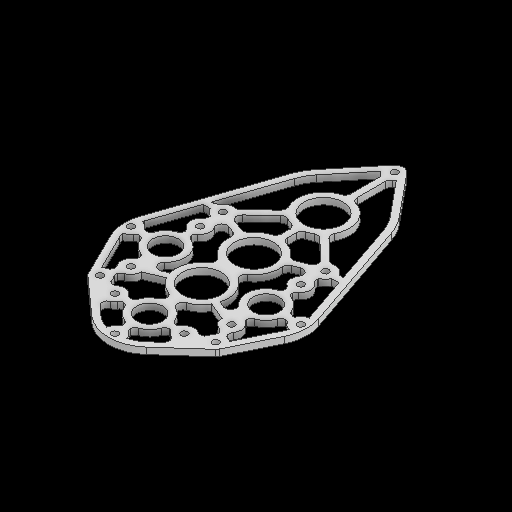
# Autodesk Inventor part: gb5_001_plate
Saved by Autodesk Inventor 2027.1 (Build 311270010, 270A)
## iProperties
Created: 2026-10-31
Part Number: gb5_001_plate
Material: Generic
Document SubType Name: Modeling
Designer: Stanley Ruangsuwan
Density: 1 g/cm^3
Appearance: Default
Author: Stanley Ruangsuwan
Autodesk Inventor part; units mm, degrees
ref_plane "YZ Plane" through (0, 0, 0) normal (1, 0, 0) x (0, 1, 0)
ref_plane "XZ Plane" through (0, 0, 0) normal (0, 1, 0) x (-1, 0, 0)
ref_plane "XY Plane" through (0, 0, 0) normal (0, 0, 1) x (1, 0, 0)
sketch "Sketch1" plane through (0, 0, 0) normal (0, 1, 0) x (-1, 0, 0)
  circle A0 centre (36.7799, -18.3459) radius 25.4 construction
  circle A1 centre (0, 30.0609) radius 25.4 construction
  circle A2 centre (-36.7799, -18.3459) radius 25.4 construction
  circle A3 centre (36.7799, -18.3459) radius 30.0609
  circle A4 centre (-36.7799, -18.3459) radius 30.0609
  circle A5 centre (0, 30.0609) radius 30.0609
  circle A6 centre (36.7799, -18.3459) radius 13.97 construction
  circle A7 centre (-36.7799, -18.3459) radius 13.97 construction
  circle A8 centre (0, 30.0609) radius 13.97 construction
  circle A9 centre (0, -8.1153) radius 26.67 construction
  circle A10 centre (0, -8.1153) radius 14.2875
  circle A11 centre (0, -46.2915) radius 13.97 construction
  circle A12 centre (0, -97.1677) radius 39.37
  circle A13 centre (36.7799, -43.7459) radius 2.4892
  circle A14 centre (54.7404, -36.3064) radius 2.4892
  circle A15 centre (62.1799, -18.3459) radius 2.4892
  circle A16 centre (54.7404, -0.3853) radius 2.4892
  circle A17 centre (36.7799, 7.0541) radius 2.4892
  line L0 (0, -8.1153) -> (0, -46.2915) construction
  circle A18 centre (-36.7799, -43.7459) radius 2.4892
  circle A19 centre (-54.7404, -36.3064) radius 2.4892
  circle A20 centre (-62.1799, -18.3459) radius 2.4892
  circle A21 centre (-54.7404, -0.3853) radius 2.4892
  circle A22 centre (-36.7799, 7.0541) radius 2.4892
  circle A23 centre (0, -46.2915) radius 14.2875
  circle A24 centre (0, -97.1677) radius 14.2875
  circle A25 centre (0, 30.0609) radius 9.525
  circle A26 centre (36.7799, -18.3459) radius 9.525
  circle A27 centre (-36.7799, -18.3459) radius 9.525
  circle A28 centre (25.4, 30.0609) radius 2.4892
  circle A29 centre (17.9605, 48.0214) radius 2.4892
  circle A30 centre (0, 55.4609) radius 2.4892
  circle A31 centre (-17.9605, 48.0214) radius 2.4892
  circle A32 centre (-25.4, 30.0609) radius 2.4892
  circle A33 centre (37.5551, -61.0997) radius 2.4892
  circle A34 centre (37.5551, -61.0997) radius 6.35 construction
  line L1 (32.9752, -65.4983) -> (28.3953, -69.8968) construction
  line L2 (37.44, -54.7508) -> (37.3249, -48.4018) construction
  circle A35 centre (-37.5551, -61.0997) radius 2.4892
  circle A36 centre (-37.5551, -61.0997) radius 6.35 construction
  line L3 (-32.9752, -65.4983) -> (-28.3953, -69.8968) construction
  line L4 (-37.44, -54.7508) -> (-37.3249, -48.4018) construction
  circle A37 centre (42.3367, 24.0525) radius 2.4892
  circle A38 centre (42.3367, 24.0525) radius 6.35
  line L5 (41.5115, 17.7563) -> (40.6863, 11.4601) construction
  line L6 (36.0497, 24.9447) -> (29.7627, 25.837) construction
  circle A39 centre (-42.3367, 24.0525) radius 2.4892
  circle A40 centre (-42.3367, 24.0525) radius 6.35
  line L7 (20.0185, 52.4867) -> (46.5653, 28.7896)
  line L8 (48.0338, 26.857) -> (63.75, -5.0693)
  line L9 (-20.0185, 52.4867) -> (-46.5653, 28.7896)
  line L10 (-48.0338, 26.857) -> (-63.75, -5.0693)
  circle A41 centre (0, -149.2377) radius 2.4892
  circle A42 centre (0, -149.2377) radius 6.35
  line L11 (0, -142.8877) -> (0, -136.5377) construction
  line L12 (-65.225, -28.0686) -> (-37.2539, -109.9014)
  line L13 (65.225, -28.0686) -> (37.2539, -109.9014)
  line L14 (30.4414, -122.134) -> (4.9099, -153.2645)
  line L15 (-30.4414, -122.134) -> (-4.9099, -153.2645)
  point P0 (0, 0)
  point P1 (36.2511, 22.2392)
  point P2 (36.3744, 26.2373)
  dimension "d1" = 50.8
  dimension "d5" = 60.1218
  dimension "d8" = 27.94
  dimension "d9" = 53.34
  dimension "d10" = 38.1762
  dimension "d11" = 38.1762
  dimension "d13" = 38.1762
  dimension "d14" = 28.575
  dimension "d15" = 60.7945
  dimension "d16" = 38.1762
  dimension "d17" = 78.74
  dimension "d18" = 50.8762
  dimension "d19" = 4.9784
  dimension "d22" = 180
  dimension "d29" = 28.575
  dimension "d31" = 19.05
  dimension "d33" = 4.9784
  dimension "d36" = 180
  dimension "d38" = 4.9784
  dimension "d41" = 12.7
  dimension "d42" = 6.35
  dimension "d43" = 4.9784
  dimension "d44" = 12.7
  dimension "d47" = 4.9784
  dimension "d48" = 12.7
  constraints: 41 centre point, 32 end point, 31 point on circle, 17 coincident, 16 tangent, 13 symmetric about line, 10 point on line, 8 equal radius, 8 vertical alignment, 4 equal length, 3 horizontal alignment, 2 vertical, 32 other
  measures "d5" diameter of A5
  measures "d8" diameter of A8
  measures "d9" diameter of A9
  measures "d10" distance of A9.centre A6.centre
  measures "d11" distance of A7.centre A9.centre
  measures "d13" distance of A8.centre A9.centre
  measures "d14" diameter of A10
  measures "d15" distance of A5.centre A7.centre
  measures "d16" distance of A9.centre L0.end
  measures "d17" diameter of A12
  measures "d18" distance of L0.end A12.centre
  measures "d19" diameter of A13
  measures "d29" diameter of A24
  measures "d31" diameter of A26
  measures "d33" diameter of A28
  measures "d38" diameter of A33
  measures "d41" diameter of A34
  measures "d42" distance of L1.start L1.end
  measures "d43" diameter of A37
  measures "d44" diameter of A38
  measures "d47" diameter of A41
  measures "d48" diameter of A42
extrude "Extrusion1" add sketch "Sketch1" along normal blind 4.7625 contours A3 A10 | A3 A10 A5 L7 A38 L8 | L13 A12 A23 L12 A4 A10 A3 | A38 | A12 A23 | A10 A5 | A4 A10 | L14 A42 L15 A12 | A10 A4 L10 A40 L9 A5 | A42 | A40 picked at (29.5618, -37.6747) picked at (-8.372, -68.1952) picked at (-19.4323, 22.8031) picked at (-29.5618, -37.6747)
sketch "Sketch2" plane through (0, 4.7625, 0) normal (0, 1, 0) x (1, 0, 0)
  arc A0 (46.5653, -28.7896) -> (48.0338, -26.857) centre (42.3367, -24.0525) ccw projected
  line L0 (48.0338, -26.857) -> (63.75, 5.0693) projected
  arc A1 (63.75, 5.0693) -> (65.225, 28.0686) centre (36.7799, 18.3459) ccw projected
  line L1 (65.225, 28.0686) -> (37.2539, 109.9014) projected
  arc A2 (37.2539, 109.9014) -> (30.4414, 122.134) centre (0, 97.1677) ccw projected
  line L2 (30.4414, 122.134) -> (4.9099, 153.2645) projected
  arc A3 (4.9099, 153.2645) -> (-4.9099, 153.2645) centre (0, 149.2377) ccw projected
  line L3 (-4.9099, 153.2645) -> (-30.4414, 122.134) projected
  arc A4 (-30.4414, 122.134) -> (-37.2539, 109.9014) centre (0, 97.1677) ccw projected
  line L4 (-37.2539, 109.9014) -> (-65.225, 28.0686) projected
  arc A5 (-65.225, 28.0686) -> (-63.75, 5.0693) centre (-36.7799, 18.3459) ccw projected
  line L5 (-63.75, 5.0693) -> (-48.0338, -26.857) projected
  arc A6 (-48.0338, -26.857) -> (-46.5653, -28.7896) centre (-42.3367, -24.0525) ccw projected
  line L6 (-46.5653, -28.7896) -> (-20.0185, -52.4867) projected
  arc A7 (-20.0185, -52.4867) -> (20.0185, -52.4867) centre (0, -30.0609) ccw projected
  line L7 (20.0185, -52.4867) -> (46.5653, -28.7896) projected
  circle A8 centre (42.3367, -24.0525) radius 2.4892 projected
  circle A9 centre (-42.3367, -24.0525) radius 2.4892 projected
  circle A10 centre (0, -30.0609) radius 9.525 projected
  circle A11 centre (-25.4, -30.0609) radius 2.4892 projected
  circle A12 centre (-17.9605, -48.0214) radius 2.4892 construction
  circle A13 centre (0, -55.4609) radius 2.4892 projected
  circle A14 centre (17.9605, -48.0214) radius 2.4892 construction
  circle A15 centre (25.4, -30.0609) radius 2.4892 projected
  circle A16 centre (0, 46.2915) radius 14.2875 projected
  circle A17 centre (37.5551, 61.0997) radius 2.4892 projected
  circle A18 centre (-37.5551, 61.0997) radius 2.4892 projected
  circle A19 centre (-36.7799, 18.3459) radius 9.525 projected
  circle A20 centre (-36.7799, -7.0541) radius 2.4892 projected
  circle A21 centre (-54.7404, 0.3853) radius 2.4892 construction
  circle A22 centre (-62.1799, 18.3459) radius 2.4892 projected
  circle A23 centre (-54.7404, 36.3064) radius 2.4892 construction
  circle A24 centre (-36.7799, 43.7459) radius 2.4892 projected
  circle A25 centre (36.7799, 18.3459) radius 9.525 projected
  circle A26 centre (36.7799, -7.0541) radius 2.4892 projected
  circle A27 centre (54.7404, 0.3853) radius 2.4892 construction
  circle A28 centre (62.1799, 18.3459) radius 2.4892 projected
  circle A29 centre (54.7404, 36.3064) radius 2.4892 construction
  circle A30 centre (36.7799, 43.7459) radius 2.4892 projected
  circle A31 centre (0, 97.1677) radius 14.2875 projected
  circle A32 centre (0, 8.1153) radius 14.2875 projected
  circle A33 centre (0, 149.2377) radius 2.4892 projected
  line L8 (32.7473, 108.361) -> (60.7185, 26.5283)
  arc A34 (59.4772, 7.1727) -> (60.7185, 26.5283) centre (36.7799, 18.3459) ccw
  line L9 (59.4772, 7.1727) -> (43.7609, -24.7536)
  arc A35 (43.3938, -25.2367) -> (43.7609, -24.7536) centre (42.3367, -24.0525) ccw
  line L10 (43.3938, -25.2367) -> (16.847, -48.9339)
  arc A36 (-16.847, -48.9339) -> (16.847, -48.9339) centre (0, -30.0609) ccw
  line L11 (-16.847, -48.9339) -> (-43.3938, -25.2367)
  arc A37 (-43.7609, -24.7536) -> (-43.3938, -25.2367) centre (-42.3367, -24.0525) ccw
  line L12 (-43.7609, -24.7536) -> (-59.4772, 7.1727)
  arc A38 (-60.7185, 26.5283) -> (-59.4772, 7.1727) centre (-36.7799, 18.3459) ccw
  line L13 (-60.7185, 26.5283) -> (-32.7473, 108.361)
  arc A39 (-26.759, 119.1139) -> (-32.7473, 108.361) centre (0, 97.1677) ccw
  line L14 (-26.759, 119.1139) -> (-1.2275, 150.2444)
  arc A40 (1.2275, 150.2444) -> (-1.2275, 150.2444) centre (0, 149.2377) ccw
  line L15 (1.2275, 150.2444) -> (26.759, 119.1139)
  arc A41 (32.7473, 108.361) -> (26.759, 119.1139) centre (0, 97.1677) ccw
  circle A42 centre (62.1799, 18.3459) radius 7.2517
  circle A43 centre (36.7799, -7.0541) radius 7.2517
  circle A44 centre (36.7799, 43.7459) radius 7.2517
  circle A45 centre (37.5551, 61.0997) radius 7.2517
  circle A46 centre (0, -55.4609) radius 7.2517
  circle A47 centre (25.4, -30.0609) radius 7.2517
  circle A48 centre (42.3367, -24.0525) radius 7.2517
  circle A49 centre (0, 149.2377) radius 7.2517
  line L16 (0, 32.004) -> (0, 60.579)
  circle A50 centre (36.7799, 18.3459) radius 14.2875
  circle A51 centre (0, -30.0609) radius 14.2875
  circle A52 centre (0, 8.1153) radius 19.05
  circle A53 centre (0, 46.2915) radius 19.05
  circle A54 centre (0, 97.1677) radius 19.05
  circle A55 centre (-62.1799, 18.3459) radius 7.2517
  circle A56 centre (-36.7799, -7.0541) radius 7.2517
  circle A57 centre (-36.7799, 43.7459) radius 7.2517
  circle A58 centre (-37.5551, 61.0997) radius 7.2517
  circle A59 centre (-25.4, -30.0609) radius 7.2517
  circle A60 centre (-42.3367, -24.0525) radius 7.2517
  circle A61 centre (-36.7799, 18.3459) radius 14.2875
  line L17 (51.0674, 18.3459) -> (54.9282, 18.3459)
  line L18 (36.7799, 4.0584) -> (36.7799, 0.1976)
  line L19 (36.7799, 32.6334) -> (36.7799, 36.4942)
  line L20 (23.0149, 14.5171) -> (18.3532, 13.2204)
  line L21 (30.076, -4.2892) -> (17.6109, 0.8519)
  line L22 (18.1483, -30.0609) -> (14.2875, -30.0609)
  line L23 (0, -44.3484) -> (0, -48.2092)
  line L24 (37.1035, 50.9903) -> (37.2315, 53.8553)
  line L25 (44.8068, 61.0997) -> (48.9017, 61.0997)
  line L26 (30.8089, 58.4397) -> (17.7221, 53.2794)
  line L27 (32.3249, 66.1229) -> (13.7397, 83.9721)
  line L28 (0, 116.2177) -> (0, 141.986)
  line L29 (-51.0674, 18.3459) -> (-54.9282, 18.3459)
  line L30 (-36.7799, 4.0584) -> (-36.7799, 0.1976)
  line L31 (-36.7799, 32.6334) -> (-36.7799, 36.4942)
  line L32 (-23.0149, 14.5171) -> (-18.3532, 13.2204)
  line L33 (-30.076, -4.2892) -> (-17.6109, 0.8519)
  line L34 (-18.1483, -30.0609) -> (-14.2875, -30.0609)
  line L35 (-37.1035, 50.9903) -> (-37.2315, 53.8553)
  line L36 (-44.8068, 61.0997) -> (-48.9017, 61.0997)
  line L37 (-30.8089, 58.4397) -> (-17.7221, 53.2794)
  line L38 (-32.3249, 66.1229) -> (-13.7397, 83.9721)
  line L39 (-34.2643, 67.5618) -> (-15.2814, 85.7931)
  line L40 (-33.2285, 61.9534) -> (-11.9825, 82.3581)
  line L41 (-33.2285, 61.9534) -> (-16.7096, 55.4399)
  line L42 (-26.1954, 54.0609) -> (-18.4566, 51.0094)
  arc A62 (-28.7315, 66.2724) -> (-27.428, 59.6662) centre (-25.9607, 63.3874) ccw
  line L43 (-39.4644, 50.4823) -> (-39.6283, 54.1507)
  line L44 (-44.4047, 58.7185) -> (-49.7156, 58.7185)
  line L45 (-44.4047, 63.481) -> (-48.0877, 63.481)
  line L46 (-39.1611, 32.4335) -> (-39.1611, 36.8963)
  line L47 (-34.3986, 32.4335) -> (-34.3986, 36.8963)
  line L48 (-22.8539, 1.2653) -> (-18.3807, 3.1102)
  line L49 (-39.1611, 4.2582) -> (-39.1611, -0.2046)
  line L50 (-50.8675, 20.7271) -> (-55.3303, 20.7271)
  arc A63 (-26.1954, 54.0609) -> (-30.9039, 47.9956) centre (-27.6627, 50.3397) ccw
  arc A64 (-27.0733, 7.8618) -> (-22.8539, 1.2653) centre (-24.3707, 4.9428) ccw
  line L51 (-29.5398, -6.6439) -> (-16.5649, -1.2925)
  arc A65 (-39.1611, 1.2231) -> (-41.7542, 4.9522) centre (-43.1391, 1.2231) ccw
  arc A66 (-40.8864, -1.0772) -> (-39.1611, 2.2015) centre (-43.1391, 2.2015) ccw
  line L52 (-50.8675, 15.9646) -> (-55.3303, 15.9646)
  arc A67 (-56.203, 22.4524) -> (-52.9242, 20.7271) centre (-52.9242, 24.7051) ccw
  arc A68 (-52.9242, 15.9646) -> (-56.203, 14.2393) centre (-52.9242, 11.9866) ccw
  arc A69 (-50.1735, 13.3716) -> (-53.9026, 15.9646) centre (-53.9026, 11.9866) ccw
  arc A70 (-53.9026, 20.7271) -> (-50.1735, 23.3202) centre (-53.9026, 24.7051) ccw
  arc A71 (-46.8223, 63.481) -> (-43.5278, 65.2124) centre (-46.8223, 67.481) ccw
  arc A72 (-39.6616, 54.897) -> (-43.6577, 58.7185) centre (-43.6577, 54.7185) ccw
  arc A73 (-41.155, 49.529) -> (-39.5723, 52.8975) centre (-43.5683, 52.719) ccw
  arc A74 (-39.1611, 34.4787) -> (-40.8926, 37.7732) centre (-43.1611, 34.4787) ccw
  arc A75 (-41.7653, 31.7353) -> (-39.1611, 35.4839) centre (-43.1611, 35.4839) ccw
  arc A76 (-32.6672, 37.7732) -> (-34.3986, 34.4787) centre (-30.3986, 34.4787) ccw
  arc A77 (-34.3986, 35.4839) -> (-31.7944, 31.7353) centre (-30.3986, 35.4839) ccw
  arc A78 (-17.6243, 83.5429) -> (-16.8558, 88.2916) centre (-20.395, 86.4278) ccw
  arc A79 (-9.5495, 80.6841) -> (-14.3254, 80.108) centre (-11.5547, 77.223) ccw
  arc A80 (-36.0962, 68.2032) -> (-32.5207, 69.2364) centre (-35.2914, 72.1214) ccw
  line L53 (-18.5504, -32.4422) -> (-14.0877, -32.4422)
  line L54 (-18.5504, -27.6797) -> (-14.0877, -27.6797)
  arc A81 (-19.4231, -25.9543) -> (-16.1444, -27.6797) centre (-16.1444, -23.7016) ccw
  arc A82 (-17.1228, -27.6797) -> (-13.3936, -25.0866) centre (-17.1228, -23.7016) ccw
  arc A83 (-13.3936, -35.0352) -> (-17.1228, -32.4422) centre (-17.1228, -36.4202) ccw
  arc A84 (-16.1444, -32.4422) -> (-19.4231, -34.1675) centre (-16.1444, -36.4202) ccw
  line L55 (-2.3813, 116.0683) -> (-2.3813, 142.3881)
  arc A85 (-2.3813, 139.9705) -> (-4.1127, 143.265) centre (-6.3813, 139.9705) ccw
  arc A86 (-5.2739, 115.4731) -> (-2.3813, 119.3168) centre (-6.3813, 119.3168) ccw
  line L56 (34.2643, 67.5618) -> (15.2814, 85.7931)
  line L57 (33.2285, 61.9534) -> (11.9825, 82.3581)
  line L58 (33.2285, 61.9534) -> (16.7096, 55.4399)
  line L59 (26.1954, 54.0609) -> (18.4566, 51.0094)
  arc A87 (27.428, 59.6662) -> (28.7315, 66.2724) centre (25.9607, 63.3874) ccw
  line L60 (39.4644, 50.4823) -> (39.6283, 54.1507)
  line L61 (44.4047, 58.7185) -> (49.7156, 58.7185)
  line L62 (44.4047, 63.481) -> (48.0877, 63.481)
  line L63 (39.1611, 32.4335) -> (39.1611, 36.8963)
  line L64 (34.3986, 32.4335) -> (34.3986, 36.8963)
  line L65 (39.1611, 4.2582) -> (39.1611, -0.2046)
  line L66 (50.8675, 20.7271) -> (55.3303, 20.7271)
  arc A88 (30.9039, 47.9956) -> (26.1954, 54.0609) centre (27.6627, 50.3397) ccw
  arc A89 (22.8539, 1.2653) -> (27.0733, 7.8618) centre (24.3707, 4.9428) ccw
  line L67 (29.5398, -6.6439) -> (16.5649, -1.2925)
  arc A90 (41.7542, 4.9522) -> (39.1611, 1.2231) centre (43.1391, 1.2231) ccw
  arc A91 (39.1611, 2.2015) -> (40.8864, -1.0772) centre (43.1391, 2.2015) ccw
  line L68 (50.8675, 15.9646) -> (55.3303, 15.9646)
  arc A92 (56.203, 14.2393) -> (52.9242, 15.9646) centre (52.9242, 11.9866) ccw
  arc A93 (53.9026, 15.9646) -> (50.1735, 13.3716) centre (53.9026, 11.9866) ccw
  arc A94 (50.1735, 23.3202) -> (53.9026, 20.7271) centre (53.9026, 24.7051) ccw
  arc A95 (43.5278, 65.2124) -> (46.8223, 63.481) centre (46.8223, 67.481) ccw
  arc A96 (43.6577, 58.7185) -> (39.6616, 54.897) centre (43.6577, 54.7185) ccw
  arc A97 (39.5723, 52.8975) -> (41.155, 49.529) centre (43.5683, 52.719) ccw
  arc A98 (40.8926, 37.7732) -> (39.1611, 34.4787) centre (43.1611, 34.4787) ccw
  arc A99 (39.1611, 35.4839) -> (41.7653, 31.7353) centre (43.1611, 35.4839) ccw
  arc A100 (34.3986, 34.4787) -> (32.6672, 37.7732) centre (30.3986, 34.4787) ccw
  arc A101 (31.7944, 31.7353) -> (34.3986, 35.4839) centre (30.3986, 35.4839) ccw
  arc A102 (16.8558, 88.2916) -> (17.6243, 83.5429) centre (20.395, 86.4278) ccw
  arc A103 (14.3254, 80.108) -> (9.5495, 80.6841) centre (11.5547, 77.223) ccw
  arc A104 (32.5207, 69.2364) -> (36.0962, 68.2032) centre (35.2914, 72.1214) ccw
  line L69 (18.5504, -32.4422) -> (14.0877, -32.4422)
  arc A105 (16.1444, -27.6797) -> (19.4231, -25.9543) centre (16.1444, -23.7016) ccw
  arc A106 (13.3936, -25.0866) -> (17.1228, -27.6797) centre (17.1228, -23.7016) ccw
  arc A107 (17.1228, -32.4421) -> (13.3936, -35.0352) centre (17.1228, -36.4202) ccw
  arc A108 (19.4231, -34.1675) -> (16.1444, -32.4422) centre (16.1444, -36.4202) ccw
  line L70 (2.3812, 116.0683) -> (2.3812, 142.3881)
  arc A109 (4.1127, 143.265) -> (2.3812, 139.9705) centre (6.3812, 139.9705) ccw
  arc A110 (2.3812, 119.3168) -> (5.2739, 115.4731) centre (6.3812, 119.3168) ccw
  line L71 (22.8539, 1.2653) -> (18.3807, 3.1102)
  line L72 (-2.3813, -44.1486) -> (-2.3813, -48.6113)
  line L73 (2.3812, -44.1486) -> (2.3812, -48.6113)
  line L74 (17.1228, -27.6797) -> (16.1444, -27.6797)
  arc A111 (4.9743, -43.4545) -> (2.3813, -47.1837) centre (6.3593, -47.1837) ccw
  arc A112 (2.3813, -46.2053) -> (4.1066, -49.484) centre (6.3593, -46.2053) ccw
  arc A113 (-19.7316, 56.6315) -> (-15.0948, 57.9125) centre (-18.2643, 60.3527) ccw
  arc A114 (-18.964, 48.1001) -> (-21.4786, 52.201) centre (-22.9459, 48.4798) ccw
  arc A115 (15.0948, 57.9125) -> (19.7316, 56.6315) centre (18.2643, 60.3527) ccw
  arc A116 (21.4786, 52.201) -> (18.964, 48.1001) centre (22.9459, 48.4798) ccw
  arc A117 (-2.3812, -47.1837) -> (-4.9743, -43.4545) centre (-6.3593, -47.1837) ccw
  arc A118 (-4.1066, -49.484) -> (-2.3812, -46.2053) centre (-6.3593, -46.2053) ccw
  line L75 (-39.0331, -13.9469) -> (-40.0834, -17.1597)
  line L76 (-32.2344, -27.6363) -> (-35.5023, -26.477)
  line L77 (-41.1716, -12.8248) -> (-42.4717, -16.802)
  line L78 (-36.6448, -14.3046) -> (-37.945, -18.2818)
  line L79 (-31.0592, -25.5266) -> (-35.0851, -24.0984)
  line L80 (-32.6516, -30.015) -> (-36.6774, -28.5868)
  arc A119 (-41.9192, -15.1117) -> (-42.5403, -11.4592) centre (-45.7003, -13.8756) ccw
  arc A120 (-43.9689, -16.9868) -> (-41.9192, -15.1117) centre (-44.6049, -14.2337) ccw
  arc A121 (-35.2325, -22.597) -> (-33.4091, -24.6929) centre (-32.4644, -22.0299) ccw
  arc A122 (-35.0014, -29.1814) -> (-37.738, -29.6596) centre (-35.9462, -31.8444) ccw
  arc A123 (-32.5041, -31.5163) -> (-34.3275, -29.4204) centre (-35.2723, -32.0834) ccw
  arc A124 (-32.7352, -24.932) -> (-29.9986, -24.4538) centre (-31.7905, -22.269) ccw
  arc A125 (-34.7337, -14.0112) -> (-37.3924, -16.5915) centre (-33.6113, -17.8276) ccw
  arc A126 (-37.3924, -16.5915) -> (-36.8461, -19.3153) centre (-34.7066, -17.4695) ccw
  line L81 (39.0331, -13.9469) -> (40.0834, -17.1597)
  line L82 (32.2344, -27.6363) -> (35.5023, -26.477)
  line L83 (41.1716, -12.8248) -> (42.4717, -16.802)
  line L84 (36.6448, -14.3046) -> (37.945, -18.2818)
  line L85 (31.0592, -25.5266) -> (35.0851, -24.0984)
  line L86 (32.6516, -30.015) -> (36.6774, -28.5868)
  arc A127 (42.5403, -11.4592) -> (41.9192, -15.1117) centre (45.7003, -13.8756) ccw
  arc A128 (41.9192, -15.1117) -> (43.9689, -16.9868) centre (44.6049, -14.2337) ccw
  arc A129 (33.4091, -24.6929) -> (35.2325, -22.597) centre (32.4644, -22.0299) ccw
  arc A130 (37.738, -29.6596) -> (35.0014, -29.1814) centre (35.9462, -31.8444) ccw
  arc A131 (34.3275, -29.4204) -> (32.5041, -31.5163) centre (35.2723, -32.0834) ccw
  arc A132 (29.9986, -24.4538) -> (32.7352, -24.932) centre (31.7905, -22.269) ccw
  arc A133 (37.3924, -16.5915) -> (34.7337, -14.0112) centre (33.6113, -17.8276) ccw
  arc A134 (36.8461, -19.3153) -> (37.3924, -16.5915) centre (34.7066, -17.4695) ccw
  line L87 (0, 97.1677) -> (0, -30.0609)
  line L88 (-2.3813, 78.2671) -> (-2.3812, -15.9732)
  line L89 (2.3812, 78.2671) -> (2.3813, -15.9732)
  arc A135 (-2.3813, 75.0186) -> (-5.2739, 78.8623) centre (-6.3813, 75.0186) ccw
  arc A136 (-5.2739, 64.5969) -> (-2.3813, 68.4406) centre (-6.3813, 68.4406) ccw
  arc A137 (-10.6786, 23.8909) -> (-10.6786, 30.5159) centre (-12.9208, 27.2034) ccw
  arc A138 (-6.1078, -17.1447) -> (-6.4595, -9.8061) centre (-7.8083, -13.5485) ccw
  arc A139 (5.2739, 78.8623) -> (2.3812, 75.0186) centre (6.3812, 75.0186) ccw
  arc A140 (2.3812, 68.4406) -> (5.2739, 64.5969) centre (6.3812, 68.4406) ccw
  arc A141 (10.6786, 30.5159) -> (10.6786, 23.8909) centre (12.9208, 27.2034) ccw
  arc A142 (6.4595, -9.8061) -> (6.1078, -17.1447) centre (7.8083, -13.5485) ccw
  arc A143 (-22.3185, -36.6253) -> (-23.2771, -43.194) centre (-20.628, -40.2263) ccw
  arc A144 (23.2771, -43.194) -> (22.3185, -36.6253) centre (20.628, -40.2263) ccw
  point P0 (0, 0)
  point P1 (36.7799, 34.5638)
  point P2 (52.9978, 18.3459)
  point P3 (0, 46.2915)
  point P4 (-61.0433, 11.1838)
  point P5 (-46.886, -18.4053)
  point P6 (-38.1152, -29.9487)
  point P7 (-7.1621, -54.3243)
  point P8 (-61.0433, 25.5079)
  point P9 (-5.7146, 144.7733)
  point P10 (5.7146, 144.7733)
  point P11 (4.1127, 143.265)
  point P12 (5.2739, 115.4731)
  point P13 (16.8558, 88.2916)
  point P14 (36.0962, 68.2032)
  point P15 (43.5278, 65.2124)
  point P16 (48.0877, 63.481)
  point P17 (15.0948, 57.9125)
  point P18 (9.5495, 80.6841)
  point P19 (61.0433, 25.5079)
  point P20 (49.7156, 58.7185)
  point P21 (41.155, 49.529)
  point P22 (50.1735, 23.3202)
  point P23 (7.1621, -54.3243)
  point P24 (38.1152, -29.9487)
  point P25 (46.886, -18.4053)
  point P26 (61.0433, 11.1838)
  point P27 (56.203, 14.2393)
  point P28 (50.1735, 13.3716)
  point P29 (40.8864, -1.0772)
  point P30 (13.3936, -35.0352)
  point P31 (16.5649, -1.2925)
  point P32 (13.3936, -25.0866)
  point P33 (21.4786, 52.201)
  point P34 (18.964, 48.1001)
  point P35 (-32.6672, 37.7732)
  point P36 (-34.3986, 34.4787)
  point P37 (-34.3986, 35.4839)
  point P38 (-31.7944, 31.7353)
  point P39 (31.7944, 31.7353)
  point P40 (34.3986, 35.4839)
  point P41 (34.3986, 34.4787)
  point P42 (32.6672, 37.7732)
  point P43 (27.0733, 7.8618)
  point P44 (-16.6336, -32.4723)
  point P45 (-39.1913, 1.7123)
  point P46 (-53.4134, 15.9344)
  point P47 (-53.4134, 20.7573)
  point P48 (-39.1928, 34.9813)
  point P49 (39.1928, 34.9813)
  point P50 (39.1611, -0.2046)
  point P51 (2.4114, -46.6945)
  point P52 (16.6336, -32.4723)
  point P53 (53.4134, 15.9344)
  point P54 (39.1913, 1.7123)
  point P55 (16.6336, -27.6495)
  point P56 (-16.6336, -27.6495)
  point P57 (34.3669, 34.9813)
  point P58 (-34.3669, 34.9813)
  point P59 (-2.4114, -46.6945)
  point P60 (-4.9743, -43.4545)
  point P61 (-4.1066, -49.484)
  point P62 (42.5403, -11.4592)
  point P63 (2.3812, 75.0186)
  point P64 (2.3812, 68.4406)
  point P65 (5.2739, 64.5969)
  point P66 (6.4595, -9.8061)
  point P67 (6.1078, -17.1447)
  point P68 (36.8461, -19.3153)
  point P69 (34.7337, -14.0112)
  point P70 (-34.7337, -14.0112)
  point P71 (-36.8461, -19.3153)
  point P72 (23.2771, -43.194)
  point P73 (22.3185, -36.6253)
  dimension "d49" = 4.7625
  dimension "d50" = 4.7625
  dimension "d56" = 4.7625
  dimension "d57" = 4.7625
  dimension "d58" = 4.7625
  dimension "d59" = 2.3813
  dimension "d60" = 2.3813
  dimension "d61" = 2.3813
  dimension "d62" = 2.3813
  dimension "d63" = 4
  dimension "d66" = 2.3813
  dimension "d67" = 2.3813
  dimension "d68" = 2.3813
  dimension "d69" = 2.3813
  dimension "d70" = 2.3813
  dimension "d74" = 2.3813
  dimension "d75" = 2.3813
  dimension "d78" = 2.3813
  dimension "d79" = 4
  dimension "d81" = 2.3813
  dimension "d88" = 2.3813
  dimension "d89" = 2.3813
  dimension "d91" = 2.3813
  dimension "d92" = 2.3813
  dimension "d97" = 2.3813
  dimension "d98" = 2.3813
  dimension "d99" = 2.3813
  dimension "d100" = 2.3813
  dimension "d101" = 2.3813
  dimension "d102" = 2.3813
  constraints: 222 point on circle, 206 symmetric about line, 167 end point, 101 centre point, 85 point on line, 48 tangent, 37 equal radius, 23 parallel, 6 vertical, 4 coincident, 4 midpoint, 3 horizontal, 1 equal length, 1 horizontal alignment, 1 perpendicular, 1 vertical alignment, 190 other
  measures "d49" distance between parallel lines of L1 L8
  measures "d56" radial gap between concentric circles of A25 A50
  measures "d59" distance between parallel lines of L38 L39
  measures "d60" distance between parallel lines of L38 L40
  measures "d61" distance between parallel lines of L37 L41
  measures "d62" distance between parallel lines of L37 L42
  measures "d63" radius of A62
  measures "d66" distance between parallel lines of L35 L43
  measures "d67" distance between parallel lines of L36 L44
  measures "d68" distance between parallel lines of L36 L45
  measures "d69" distance between parallel lines of L31 L46
  measures "d70" distance between parallel lines of L31 L47
  measures "d74" distance between parallel lines of L33 L48
  measures "d75" distance between parallel lines of L30 L49
  measures "d78" distance between parallel lines of L29 L50
  measures "d79" radius of A63
  measures "d81" distance between parallel lines of L33 L51
  measures "d88" distance between parallel lines of L34 L53
  measures "d89" distance between parallel lines of L28 L55
  measures "d91" distance between parallel lines of L23 L72
  measures "d92" distance between parallel lines of L23 L73
  measures "d97" distance between parallel lines of L75 L77
  measures "d98" distance between parallel lines of L78 L75
  measures "d99" distance between parallel lines of L76 L79
  measures "d100" distance between parallel lines of L76 L80
  measures "d101" distance between parallel lines of L87 L88
  measures "d102" distance between parallel lines of L87 L89
extrude "Extrusion2" cut sketch "Sketch2" against normal blind 25.4 contours A48 A128 A127 A43 A91 A90 A50 A93 A92 A42 A34 L9 | L10 A36 A46 A112 A111 A51 A107 A108 A47 A144 | A36 L11 A143 A59 A84 A83 A51 A117 A118 A46 | A42 L66 A94 A50 A99 A98 A44 A97 L60 A45 L61 L8 A34 | A129 L85 A132 A47 A105 A106 A51 A142 A52 L67 A43 A133 A134 A48 | L12 A38 A55 A68 A69 A61 A65 A66 A56 A119 A120 A60 | L62 A95 A45 A104 L56 A102 A54 A110 L70 A109 A49 L15 A41 L8 | A49 A85 L55 A86 A54 A78 L39 A80 A58 A71 L45 L13 A39 L14 | A38 L13 L44 A58 L43 A73 A57 A74 A75 A61 A70 A67 A55 | A89 L71 A52 L20 A50 | A121 A60 A126 A125 A56 L51 A52 A138 A51 A82 A81 A59 A124 L79 | A44 A100 A101 A50 L20 A52 A141 A53 A116 L59 A88 | L58 A115 A53 A140 L89 A139 A54 A103 L57 A87 | A61 L32 A52 L48 A64 | A61 A77 A76 A57 A63 L42 A114 A53 A137 A52 L32 | A62 L40 A79 A54 A135 L88 A136 A53 A113 L41
sketch "Sketch3" plane through (0, 4.7625, 0) normal (0, 1, 0) x (1, 0, 0)
  line L0 (-56.8139, 1.7625) -> (-59.4772, 7.1727) projected
  arc A0 (-61.0433, 11.1838) -> (-59.4772, 7.1727) centre (-36.7799, 18.3459) ccw projected
  arc A1 (-61.0433, 11.1838) -> (-56.203, 14.2393) centre (-62.1799, 18.3459) ccw projected
  arc A2 (7.1621, -54.3243) -> (4.1066, -49.484) centre (0, -55.4609) ccw projected
  arc A3 (-16.0495, -49.6165) -> (-7.1621, -54.3243) centre (0, -30.0609) ccw projected
  arc A4 (-19.7764, -46.3189) -> (-16.0495, -49.6165) centre (-17.9605, -48.0214) ccw projected
  line L1 (-19.7764, -46.3189) -> (-23.2771, -43.194) projected
  arc A5 (-43.9689, -16.9868) -> (-46.886, -18.4053) centre (-42.3367, -24.0525) ccw projected
  line L2 (-46.886, -18.4053) -> (-54.9136, -2.0978) projected
  arc A6 (-56.8139, 1.7625) -> (-54.9136, -2.0978) centre (-54.7404, 0.3853) ccw projected
  line L3 (5.7146, 144.7733) -> (26.759, 119.1139) projected
  arc A7 (32.7473, 108.361) -> (26.759, 119.1139) centre (0, 97.1677) ccw projected
  line L4 (32.7473, 108.361) -> (48.0877, 63.481) projected
  line L5 (-48.0877, 63.481) -> (-32.7473, 108.361) projected
  arc A8 (-26.759, 119.1139) -> (-32.7473, 108.361) centre (0, 97.1677) ccw projected
  line L6 (-26.759, 119.1139) -> (-5.7146, 144.7733) projected
  arc A9 (-56.203, 22.4524) -> (-61.0433, 25.5079) centre (-62.1799, 18.3459) ccw projected
  arc A10 (-60.7185, 26.5283) -> (-61.0433, 25.5079) centre (-36.7799, 18.3459) ccw projected
  arc A11 (61.0433, 25.5079) -> (60.7185, 26.5283) centre (36.7799, 18.3459) ccw projected
  arc A12 (61.0433, 25.5079) -> (55.3303, 20.7271) centre (62.1799, 18.3459) ccw projected
  line L7 (48.0338, -26.857) -> (63.75, 5.0693) projected
  arc A13 (63.75, 5.0693) -> (65.225, 28.0686) centre (36.7799, 18.3459) ccw projected
  line L8 (65.225, 28.0686) -> (37.2539, 109.9014) projected
  arc A14 (37.2539, 109.9014) -> (30.4414, 122.134) centre (0, 97.1677) ccw projected
  line L9 (30.4414, 122.134) -> (4.9099, 153.2645) projected
  arc A15 (4.9099, 153.2645) -> (-4.9099, 153.2645) centre (0, 149.2377) ccw projected
  line L10 (-4.9099, 153.2645) -> (-30.4414, 122.134) projected
  arc A16 (-30.4414, 122.134) -> (-37.2539, 109.9014) centre (0, 97.1677) ccw projected
  line L11 (-37.2539, 109.9014) -> (-65.225, 28.0686) projected
  arc A17 (-65.225, 28.0686) -> (-63.75, 5.0693) centre (-36.7799, 18.3459) ccw projected
  line L12 (-63.75, 5.0693) -> (-48.0338, -26.857) projected
  line L13 (-46.5653, -28.7896) -> (-20.0185, -52.4867) projected
  arc A18 (-20.0185, -52.4867) -> (20.0185, -52.4867) centre (0, -30.0609) ccw projected
  line L14 (20.0185, -52.4867) -> (46.5653, -28.7896) projected
  arc A19 (7.1621, -54.3243) -> (16.0495, -49.6165) centre (0, -30.0609) ccw projected
  arc A20 (56.203, 14.2393) -> (61.0433, 11.1838) centre (62.1799, 18.3459) ccw projected
  arc A21 (59.4772, 7.1727) -> (61.0433, 11.1838) centre (36.7799, 18.3459) ccw projected
  line L15 (59.4772, 7.1727) -> (56.8139, 1.7625) projected
  arc A22 (54.9136, -2.0978) -> (56.8139, 1.7625) centre (54.7404, 0.3853) ccw projected
  line L16 (54.9136, -2.0978) -> (46.886, -18.4053) projected
  arc A23 (36.8461, -19.3153) -> (35.2325, -22.597) centre (42.3367, -24.0525) ccw projected
  line L17 (23.2771, -43.194) -> (19.7764, -46.3189) projected
  arc A24 (16.0495, -49.6165) -> (19.7764, -46.3189) centre (17.9605, -48.0214) ccw projected
  circle A25 centre (0, 149.2377) radius 2.4892 projected
  line L18 (-43.7609, -24.7536) -> (-59.4772, 7.1727)
  arc A26 (-60.7185, 26.5283) -> (-59.4772, 7.1727) centre (-36.7799, 18.3459) ccw
  line L19 (-60.7185, 26.5283) -> (-32.7473, 108.361)
  arc A27 (-26.759, 119.1139) -> (-32.7473, 108.361) centre (0, 97.1677) ccw
  line L20 (-26.759, 119.1139) -> (-1.2275, 150.2444)
  arc A28 (1.2275, 150.2444) -> (-1.2275, 150.2444) centre (0, 149.2377) ccw
  line L21 (1.2275, 150.2444) -> (26.759, 119.1139)
  arc A29 (32.7473, 108.361) -> (26.759, 119.1139) centre (0, 97.1677) ccw
  line L22 (32.7473, 108.361) -> (60.7185, 26.5283)
  arc A30 (59.4772, 7.1727) -> (60.7185, 26.5283) centre (36.7799, 18.3459) ccw
  line L23 (59.4772, 7.1727) -> (43.7609, -24.7536)
  arc A31 (43.3938, -25.2367) -> (43.7609, -24.7536) centre (42.3367, -24.0525) ccw
  line L24 (43.3938, -25.2367) -> (16.847, -48.9339)
  arc A32 (-16.847, -48.9339) -> (16.847, -48.9339) centre (0, -30.0609) ccw
  line L25 (-16.847, -48.9339) -> (-43.3938, -25.2367)
  arc A33 (-43.7609, -24.7536) -> (-43.3938, -25.2367) centre (-42.3367, -24.0525) ccw
  arc A34 (-4.1066, -49.484) -> (-7.1621, -54.3243) centre (0, -55.4609) ccw projected
  arc A35 (-53.4134, 15.9344) -> (-56.203, 14.2393) centre (-52.9242, 11.9866) ccw projected
  arc A36 (-50.1735, 13.3716) -> (-53.4134, 15.9344) centre (-53.9026, 11.9866) ccw projected
  arc A37 (-50.1735, 13.3716) -> (-41.7542, 4.9522) centre (-36.7799, 18.3459) ccw projected
  arc A38 (-39.1913, 1.7123) -> (-41.7542, 4.9522) centre (-43.1391, 1.2231) ccw projected
  arc A39 (-40.8864, -1.0772) -> (-39.1913, 1.7123) centre (-43.1391, 2.2015) ccw projected
  arc A40 (-40.8864, -1.0772) -> (-42.5403, -11.4592) centre (-36.7799, -7.0541) ccw projected
  arc A41 (-41.9192, -15.1117) -> (-42.5403, -11.4592) centre (-45.7003, -13.8756) ccw projected
  arc A42 (-43.9689, -16.9868) -> (-41.9192, -15.1117) centre (-44.6049, -14.2337) ccw projected
  arc A43 (2.4114, -46.6945) -> (4.1066, -49.484) centre (6.3593, -46.2053) ccw projected
  arc A44 (4.9743, -43.4545) -> (2.4114, -46.6945) centre (6.3593, -47.1837) ccw projected
  arc A45 (4.9743, -43.4545) -> (13.3936, -35.0352) centre (0, -30.0609) ccw projected
  arc A46 (16.6336, -32.4723) -> (13.3936, -35.0352) centre (17.1228, -36.4202) ccw projected
  arc A47 (19.4231, -34.1675) -> (16.6336, -32.4723) centre (16.1444, -36.4202) ccw projected
  arc A48 (19.4231, -34.1675) -> (22.3185, -36.6253) centre (25.4, -30.0609) ccw projected
  arc A49 (-22.3185, -36.6253) -> (-19.4231, -34.1675) centre (-25.4, -30.0609) ccw projected
  arc A50 (-16.6336, -32.4723) -> (-19.4231, -34.1675) centre (-16.1444, -36.4202) ccw projected
  arc A51 (-13.3936, -35.0352) -> (-16.6336, -32.4723) centre (-17.1228, -36.4202) ccw projected
  arc A52 (-13.3936, -35.0352) -> (-4.9743, -43.4545) centre (0, -30.0609) ccw projected
  arc A53 (-2.4114, -46.6945) -> (-4.9743, -43.4545) centre (-6.3593, -47.1837) ccw projected
  arc A54 (-4.1066, -49.484) -> (-2.4114, -46.6945) centre (-6.3593, -46.2053) ccw projected
  arc A55 (46.5653, -28.7896) -> (48.0338, -26.857) centre (42.3367, -24.0525) ccw projected
  arc A56 (-48.0338, -26.857) -> (-46.5653, -28.7896) centre (-42.3367, -24.0525) ccw projected
  line L26 (-29.5398, -6.6439) -> (-16.5649, -1.2925) projected
  arc A57 (-16.5649, -1.2925) -> (-6.4595, -9.8061) centre (0, 8.1153) ccw projected
  arc A58 (-6.1078, -17.1447) -> (-6.4595, -9.8061) centre (-7.8083, -13.5485) ccw projected
  arc A59 (-6.1078, -17.1447) -> (-13.3936, -25.0866) centre (0, -30.0609) ccw projected
  arc A60 (-16.6336, -27.6495) -> (-13.3936, -25.0866) centre (-17.1228, -23.7016) ccw projected
  arc A61 (-19.4231, -25.9543) -> (-16.6336, -27.6495) centre (-16.1444, -23.7016) ccw projected
  arc A62 (-19.4231, -25.9543) -> (-29.9986, -24.4538) centre (-25.4, -30.0609) ccw projected
  arc A63 (-32.7352, -24.932) -> (-29.9986, -24.4538) centre (-31.7905, -22.269) ccw projected
  line L27 (-32.7352, -24.932) -> (-33.4091, -24.6929) projected
  arc A64 (-35.2325, -22.597) -> (-33.4091, -24.6929) centre (-32.4644, -22.0299) ccw projected
  arc A65 (-35.2325, -22.597) -> (-36.8461, -19.3153) centre (-42.3367, -24.0525) ccw projected
  arc A66 (-37.3924, -16.5915) -> (-36.8461, -19.3153) centre (-34.7066, -17.4695) ccw projected
  arc A67 (-34.7337, -14.0112) -> (-37.3924, -16.5915) centre (-33.6113, -17.8276) ccw projected
  arc A68 (-34.7337, -14.0112) -> (-29.5398, -6.6439) centre (-36.7799, -7.0541) ccw projected
  line L28 (55.3303, 20.7271) -> (53.9026, 20.7271) projected
  arc A69 (50.1735, 23.3202) -> (53.9026, 20.7271) centre (53.9026, 24.7051) ccw projected
  arc A70 (50.1735, 23.3202) -> (41.7653, 31.7353) centre (36.7799, 18.3459) ccw projected
  arc A71 (39.1928, 34.9813) -> (41.7653, 31.7353) centre (43.1611, 35.4839) ccw projected
  arc A72 (40.8926, 37.7732) -> (39.1928, 34.9813) centre (43.1611, 34.4787) ccw projected
  arc A73 (40.8926, 37.7732) -> (41.155, 49.529) centre (36.7799, 43.7459) ccw projected
  arc A74 (39.5723, 52.8975) -> (41.155, 49.529) centre (43.5683, 52.719) ccw projected
  line L29 (39.5723, 52.8975) -> (39.6283, 54.1507) projected
  arc A75 (39.6283, 54.1507) -> (44.4047, 58.7185) centre (37.5551, 61.0997) ccw projected
  line L30 (44.4047, 58.7185) -> (49.7156, 58.7185) projected
  line L31 (49.7156, 58.7185) -> (60.7185, 26.5283) projected
  line L32 (-46.8223, 63.481) -> (-48.0877, 63.481) projected
  arc A76 (-5.7146, 144.7733) -> (-4.1127, 143.265) centre (0, 149.2377) ccw projected
  arc A77 (-2.3813, 139.9705) -> (-4.1127, 143.265) centre (-6.3813, 139.9705) ccw projected
  line L33 (-2.3813, 139.9705) -> (-2.3813, 119.3168) projected
  arc A78 (-5.2739, 115.4731) -> (-2.3813, 119.3168) centre (-6.3813, 119.3168) ccw projected
  arc A79 (-5.2739, 115.4731) -> (-16.8558, 88.2916) centre (0, 97.1677) ccw projected
  arc A80 (-17.6243, 83.5429) -> (-16.8558, 88.2916) centre (-20.395, 86.4278) ccw projected
  line L34 (-17.6243, 83.5429) -> (-32.5207, 69.2364) projected
  arc A81 (-36.0962, 68.2032) -> (-32.5207, 69.2364) centre (-35.2914, 72.1214) ccw projected
  arc A82 (-36.0962, 68.2032) -> (-43.5278, 65.2124) centre (-37.5551, 61.0997) ccw projected
  arc A83 (-46.8223, 63.481) -> (-43.5278, 65.2124) centre (-46.8223, 67.481) ccw projected
  arc A84 (13.3936, -25.0866) -> (16.6336, -27.6495) centre (17.1228, -23.7016) ccw projected
  arc A85 (13.3936, -25.0866) -> (6.1078, -17.1447) centre (0, -30.0609) ccw projected
  arc A86 (6.4595, -9.8061) -> (6.1078, -17.1447) centre (7.8083, -13.5485) ccw projected
  arc A87 (6.4595, -9.8061) -> (16.5649, -1.2925) centre (0, 8.1153) ccw projected
  line L35 (16.5649, -1.2925) -> (29.5398, -6.6439) projected
  arc A88 (29.5398, -6.6439) -> (34.7337, -14.0112) centre (36.7799, -7.0541) ccw projected
  arc A89 (37.3924, -16.5915) -> (34.7337, -14.0112) centre (33.6113, -17.8276) ccw projected
  arc A90 (36.8461, -19.3153) -> (37.3924, -16.5915) centre (34.7066, -17.4695) ccw projected
  arc A91 (33.4091, -24.6929) -> (35.2325, -22.597) centre (32.4644, -22.0299) ccw projected
  line L36 (33.4091, -24.6929) -> (32.7352, -24.932) projected
  arc A92 (29.9986, -24.4538) -> (32.7352, -24.932) centre (31.7905, -22.269) ccw projected
  arc A93 (29.9986, -24.4538) -> (19.4231, -25.9543) centre (25.4, -30.0609) ccw projected
  arc A94 (16.6336, -27.6495) -> (19.4231, -25.9543) centre (16.1444, -23.7016) ccw projected
  arc A95 (4.1127, 143.265) -> (5.7146, 144.7733) centre (0, 149.2377) ccw projected
  line L37 (48.0877, 63.481) -> (46.8223, 63.481) projected
  arc A96 (43.5278, 65.2124) -> (46.8223, 63.481) centre (46.8223, 67.481) ccw projected
  arc A97 (43.5278, 65.2124) -> (36.0962, 68.2032) centre (37.5551, 61.0997) ccw projected
  arc A98 (32.5207, 69.2364) -> (36.0962, 68.2032) centre (35.2914, 72.1214) ccw projected
  line L38 (32.5207, 69.2364) -> (17.6243, 83.5429) projected
  arc A99 (16.8558, 88.2916) -> (17.6243, 83.5429) centre (20.395, 86.4278) ccw projected
  arc A100 (16.8558, 88.2916) -> (5.2739, 115.4731) centre (0, 97.1677) ccw projected
  arc A101 (2.3812, 119.3168) -> (5.2739, 115.4731) centre (6.3812, 119.3168) ccw projected
  line L39 (2.3812, 119.3168) -> (2.3812, 139.9705) projected
  arc A102 (4.1127, 143.265) -> (2.3812, 139.9705) centre (6.3812, 139.9705) ccw projected
  arc A103 (-41.155, 49.529) -> (-40.8926, 37.7732) centre (-36.7799, 43.7459) ccw projected
  arc A104 (-39.1928, 34.9813) -> (-40.8926, 37.7732) centre (-43.1611, 34.4787) ccw projected
  arc A105 (-41.7653, 31.7353) -> (-39.1928, 34.9813) centre (-43.1611, 35.4839) ccw projected
  arc A106 (-41.7653, 31.7353) -> (-50.1735, 23.3202) centre (-36.7799, 18.3459) ccw projected
  arc A107 (-53.4134, 20.7573) -> (-50.1735, 23.3202) centre (-53.9026, 24.7051) ccw projected
  arc A108 (-56.203, 22.4524) -> (-53.4134, 20.7573) centre (-52.9242, 24.7051) ccw projected
  line L40 (-60.7185, 26.5283) -> (-49.7156, 58.7185) projected
  line L41 (-49.7156, 58.7185) -> (-44.4047, 58.7185) projected
  arc A109 (-44.4047, 58.7185) -> (-39.6283, 54.1507) centre (-37.5551, 61.0997) ccw projected
  line L42 (-39.6283, 54.1507) -> (-39.5723, 52.8975) projected
  arc A110 (-41.155, 49.529) -> (-39.5723, 52.8975) centre (-43.5683, 52.719) ccw projected
  arc A111 (46.886, -18.4053) -> (43.9689, -16.9868) centre (42.3367, -24.0525) ccw projected
  arc A112 (41.9192, -15.1117) -> (43.9689, -16.9868) centre (44.6049, -14.2337) ccw projected
  arc A113 (42.5403, -11.4592) -> (41.9192, -15.1117) centre (45.7003, -13.8756) ccw projected
  arc A114 (42.5403, -11.4592) -> (40.8864, -1.0772) centre (36.7799, -7.0541) ccw projected
  arc A115 (39.1913, 1.7123) -> (40.8864, -1.0772) centre (43.1391, 2.2015) ccw projected
  arc A116 (41.7542, 4.9522) -> (39.1913, 1.7123) centre (43.1391, 1.2231) ccw projected
  arc A117 (41.7542, 4.9522) -> (50.1735, 13.3716) centre (36.7799, 18.3459) ccw projected
  arc A118 (53.4134, 15.9344) -> (50.1735, 13.3716) centre (53.9026, 11.9866) ccw projected
  arc A119 (56.203, 14.2393) -> (53.4134, 15.9344) centre (52.9242, 11.9866) ccw projected
  arc A120 (-22.3185, -36.6253) -> (-23.2771, -43.194) centre (-20.628, -40.2263) ccw projected
  arc A121 (23.2771, -43.194) -> (22.3185, -36.6253) centre (20.628, -40.2263) ccw projected
  point P0 (0, 0)
  point P1 (-54.9136, -2.0978)
  point P2 (-19.7764, -46.3189)
  point P3 (56.8139, 1.7625)
  point P4 (54.9136, -2.0978)
  constraints: 16 end point, 16 point on circle, 8 centre point, 153 other
extrude "Extrusion3" add sketch "Sketch3" against normal blind 4.7625 contours L18 A6 | L25 A32 A4 | A32 L24 A24 | L23 A22
equation "\"d10\" = d11"
equation "\"d13\" = d11"
equation "\"d16\" = d11"
body "Solid1"
